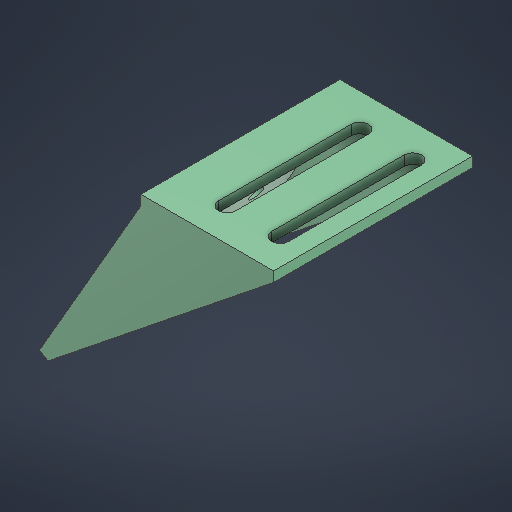
# Autodesk Inventor part: 1_1_7_3_fixation_simplifiee
Saved by Autodesk Inventor 2026 (Build 300175000, 175)
## iProperties
Created: 2025-05-11
Part Number: 1_1_7_3_fixation_simplifiee
Material: Generic
Document SubType Name: Modeling
Designer: remg9
Density: 1 g/cm^3
Appearance: Default
Author: remg9
Autodesk Inventor part; units mm, degrees
ref_plane "YZ Plane" through (0, 0, 0) normal (1, 0, 0) x (0, 1, 0)
ref_plane "XZ Plane" through (0, 0, 0) normal (0, 1, 0) x (-1, 0, 0)
ref_plane "XY Plane" through (0, 0, 0) normal (0, 0, 1) x (1, 0, 0)
sketch "Sketch1" plane through (0, 0, 0) normal (0, 1, 0) x (-1, 0, 0)
  line L0 (-20, 30) -> (20, 30)
  line L1 (20, 30) -> (20, -30)
  line L2 (20, -30) -> (-20, -30)
  line L3 (-20, -30) -> (-20, 30)
  line L4 (-20, 30) -> (20, -30) construction
  line L5 (20, 30) -> (-20, -30) construction
  point P0 (0, 0)
  dimension "d0" = 40
  dimension "d1" = 60
  constraints: 12 end point, 2 midpoint, 2 parallel, 1 horizontal, 1 perpendicular
  measures "d0" distance of L1.end L2.end
  measures "d1" distance of L0.end L1.end
extrude "Extrusion1" add sketch "Sketch1" along normal blind 3
sketch "Sketch2" plane through (0, 0, 0) normal (0, 0, 1) x (1, 0, 0)
  line L0 (-20, 0) -> (-50.5996, -53)
  line L1 (-50.5996, -53) -> (-48.0015, -54.5)
  line L2 (-48.0015, -54.5) -> (20, 0)
  line L3 (20, 0) -> (20, 3) projected
  line L4 (20, 0) -> (-20, 0) projected
  line L5 (-20, 0) -> (-20, 3) projected
  point P0 (0, 0)
  dimension "d4" = 3
  dimension "d5" = 53
  dimension "d6" = 150
  constraints: 6 end point, 4 point on line, 1 perpendicular
  measures "d4" distance of L0.end L1.end
  measures "d5" distance from line of L4 L0.end
  measures "d6" angle of L5 L0
extrude "Extrusion2" add sketch "Sketch2" along normal mid plane 60
sketch "Sketch3" plane through (0, 0, 0) normal (0, 0, 1) x (1, 0, 0)
  line L0 (-48.0015, -54.5) -> (-16.5359, 0)
  line L1 (-16.5359, 0) -> (20, 0)
  line L2 (20, 0) -> (-48.0015, -54.5)
  line L3 (-50.5996, -53) -> (-20, 0) projected
  point P0 (0, 0)
  constraints: 6 end point, 2 coincident, 1 horizontal, 1 parallel
extrude "Extrusion3" cut sketch "Sketch3" along normal mid plane 54
sketch "Sketch4" plane through (0, 3, 0) normal (0, 1, 0) x (1, 0, 0)
  line L0 (12, -20) -> (12, 20) construction
  line L1 (14.6, -20) -> (14.6, 20)
  line L2 (9.4, 20) -> (9.4, -20)
  arc A0 (9.4, -20) -> (14.6, -20) centre (12, -20) ccw
  arc A1 (14.6, 20) -> (9.4, 20) centre (12, 20) ccw
  line L3 (20, -30) -> (20, 30) projected
  line L4 (20, 30) -> (-20, 30) projected
  line L5 (4, -22.6) -> (4, 23.9773) construction
  line L6 (-4, -20) -> (-4, 20) construction
  line L7 (-6.6, -20) -> (-6.6, 20)
  line L8 (-1.4, 20) -> (-1.4, -20)
  arc A2 (-6.6, -20) -> (-1.4, -20) centre (-4, -20) ccw
  arc A3 (-1.4, 20) -> (-6.6, 20) centre (-4, 20) ccw
  point P0 (0, 0)
  point P1 (12, 0)
  point P2 (-4, 0)
  dimension "d13" = 5.2
  dimension "d14" = 40
  dimension "d15" = 8
  dimension "d16" = 30
  dimension "d17" = 16
  constraints: 18 end point, 8 point on circle, 7 symmetric about line, 4 centre point, 4 tangent, 2 vertical, 1 midpoint, 1 parallel, 2 other
  measures "d13" distance between parallel lines of L1 L2
  measures "d14" distance of L1.start L1.end
  measures "d15" distance from line of L3 point (12, 0)
  measures "d16" distance from line of L4 point (12, 0)
  measures "d17" distance between parallel lines of L3 L5
extrude "Extrusion4" cut sketch "Sketch4" against normal through all
fillet "Fillet1" radius 12 1 edges at (-16.5359, 0, 0)
sketch "Sketch5" plane through (-20, 0, -30) normal (-0.866, 0.5, 0) x (0, 0, 1)
  line L0 (38, -46.6991) -> (54, -46.6991) construction
  line L1 (60, 0) -> (60, -61.1991) projected
  line L2 (60, -61.1991) -> (0, -61.1991) projected
  line L3 (30, -9.2242) -> (30, -56.4008) construction
  line L4 (22, -46.6991) -> (6, -46.6991) construction
  point P0 (30, 10)
  point P1 (46, -27.6991)
  point P2 (14, -27.6991)
  dimension "d22" = 14
  dimension "d23" = 6
  dimension "d24" = 16
  dimension "d25" = 19
  dimension "d26" = 14.5
  dimension "d34" = 30
  constraints: 6 end point, 5 symmetric about line, 4 coincident, 1 horizontal, 1 vertical
  measures "d22" distance from line of L1 point (46, -27.699)
  measures "d23" distance from line of L1 L0.end
  measures "d24" distance of point (54, -46.699) L0.start
  measures "d25" distance from line of L0 point (46, -27.699)
  measures "d26" distance between parallel lines of L2 L0
  measures "d34" distance between parallel lines of L1 L3
hole "Hole1" at (-43.3496, -40.4426, 24) at (-43.3496, -40.4426, 8) at (-33.8496, -23.9881, 16) at (-33.8496, -23.9881, -16) at (-43.3496, -40.4426, -8) at (-43.3496, -40.4426, -24) direction (0.866, -0.5, 0) diameter 4.3 end through all
body "Solid1"
